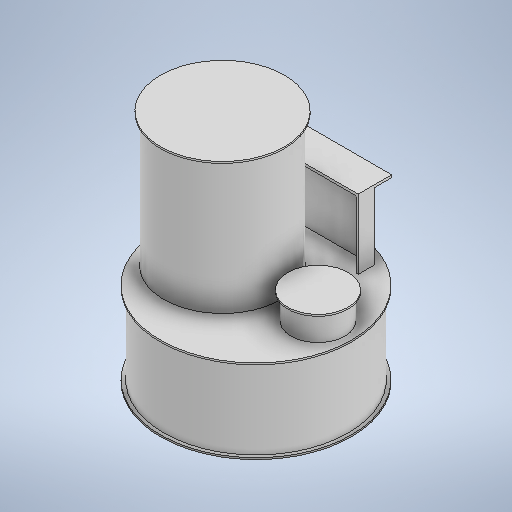
# Autodesk Inventor part: RDS-SPF-2-120-1000 Tank
Saved by Autodesk Inventor 2026 (Build 300175000, 175)
## iProperties
Created: 2026-10-27
Part Number: RDS-SPF-2-120-1000 Tank
Material: Типовые
Document SubType Name: Modeling
Designer: user
Density: 1 g/cm^3
Appearance: По умолчанию
Author: user
Autodesk Inventor part; units mm, degrees
ref_plane "YZ Plane" through (0, 0, 0) normal (1, 0, 0) x (0, 1, 0)
ref_plane "XZ Plane" through (0, 0, 0) normal (0, 1, 0) x (-1, 0, 0)
ref_plane "XY Plane" through (0, 0, 0) normal (0, 0, 1) x (1, 0, 0)
sketch "Эскиз1" plane through (0, 0, 0) normal (0, 1, 0) x (-1, 0, 0)
  circle A0 centre (0, 0) radius 550
  dimension "d0" = 1100
  constraints: 1 centre point, 1 coincident
  measures "d0" diameter of A0
extrude "Выдавливание1" add sketch "Эскиз1" along normal blind 500
sketch "Эскиз2" plane through (0, 500, 0) normal (0, 1, 0) x (1, 0, 0)
  circle A0 centre (-200, 0) radius 350
  point P0 (0, 0)
  dimension "d3" = 700
  dimension "d4" = 200
  dimension "d5" = 0
  constraints: 1 centre point
  measures "d3" diameter of A0
  measures "d4" distance of point (0, 0) A0.centre
  measures "d5" vertical distance of point (0, 0) A0.centre
extrude "Выдавливание2" add sketch "Эскиз2" along normal blind 800
shell "Оболочка1" thickness 10 removed faces 0
sketch "Эскиз3" plane through (0, 0, 0) normal (0, -1, 0) x (1, 0, 0)
  circle A0 centre (0, 0) radius 570
  dimension "d9" = 1140
  constraints: 1 centre point, 1 coincident
  measures "d9" diameter of A0
extrude "Выдавливание3" add sketch "Эскиз3" against normal blind 10
sketch "Эскиз4" plane through (0, 500, 0) normal (0, 1, 0) x (1, 0, 0)
  circle A0 centre (0, 0) radius 570
  dimension "d12" = 1140
  constraints: 1 centre point, 1 coincident
  measures "d12" diameter of A0
extrude "Выдавливание4" add sketch "Эскиз4" against normal blind 10
sketch "Эскиз5" plane through (-200, 1300, 0) normal (0, 1, 0) x (1, 0, 0)
  circle A0 centre (0, 0) radius 370
  point P0 (200, 0)
  dimension "d15" = 740
  dimension "d16" = 200
  dimension "d17" = 0
  constraints: 1 centre point
  measures "d15" diameter of A0
  measures "d16" distance of point (200, 0) A0.centre
  measures "d17" vertical distance of point (200, 0) A0.centre
extrude "Выдавливание5" add sketch "Эскиз5" against normal blind 10
sketch "Эскиз6" plane through (0, 500, 0) normal (0, 1, 0) x (1, 0, 0)
  circle A0 centre (370, 0) radius 160
  point P0 (0, 0)
  dimension "d20" = 320
  dimension "d21" = 0
  dimension "d22" = 370
  constraints: 1 centre point
  measures "d20" diameter of A0
  measures "d21" vertical distance of point (0, 0) A0.centre
  measures "d22" distance of point (0, 0) A0.centre
extrude "Выдавливание6" add sketch "Эскиз6" along normal blind 150
sketch "Эскиз7" plane through (370, 650, 0) normal (0, 1, 0) x (1, 0, 0)
  circle A0 centre (0, 0) radius 150
  point P0 (-370, 0)
  dimension "d25" = 300
  dimension "d26" = 370
  dimension "d27" = 0
  constraints: 1 centre point
  measures "d25" diameter of A0
  measures "d26" distance of A0.centre point (-370, 0)
  measures "d27" vertical distance of point (-370, 0) A0.centre
extrude "Выдавливание7" cut sketch "Эскиз7" against normal blind 160
sketch "Эскиз8" plane through (370, 650, 0) normal (0, 1, 0) x (1, 0, 0)
  circle A0 centre (0, 0) radius 180
  point P0 (-370, 0)
  dimension "d30" = 360
  dimension "d31" = 370
  dimension "d32" = 0
  constraints: 1 centre point
  measures "d30" diameter of A0
  measures "d31" distance of point (-370, 0) A0.centre
  measures "d32" vertical distance of point (-370, 0) A0.centre
extrude "Выдавливание8" add sketch "Эскиз8" along normal blind 10
sketch "Эскиз9" plane through (0, 500, 0) normal (0, 1, 0) x (1, 0, 0)
  line L0 (-250, 460) -> (250, 460)
  line L1 (250, 460) -> (250, 360)
  line L2 (250, 360) -> (240, 360)
  line L3 (240, 360) -> (240, 450)
  line L4 (240, 450) -> (-240, 450)
  line L5 (-240, 450) -> (-240, 360)
  line L6 (-240, 360) -> (-250, 360)
  line L7 (-250, 360) -> (-250, 460)
  point P0 (0, 0)
  dimension "d35" = 500
  dimension "d36" = 100
  dimension "d37" = 10
  dimension "d38" = 90
  dimension "d39" = 480
  dimension "d40" = 90
  dimension "d42" = 10
  dimension "d43" = 100
  dimension "d44" = 250
  dimension "d45" = 460
  constraints: 16 end point, 4 perpendicular, 2 horizontal, 1 point on line
  measures "d35" distance of L0.start L0.end
  measures "d36" distance of L0.end L1.end
  measures "d37" distance of L1.end L2.end
  measures "d38" distance of L2.end L3.end
  measures "d39" distance of L3.end L4.end
  measures "d40" distance of L4.end L5.end
  measures "d42" distance of L5.end L6.end
  measures "d43" distance of L6.end L0.start
  measures "d44" distance from line of L7 point (0, 0)
  measures "d45" distance from line of L0 point (0, 0)
extrude "Выдавливание9" add sketch "Эскиз9" along normal blind 400
sketch "Эскиз10" plane through (0, 900, 0) normal (0, 1, 0) x (1, 0, 0)
  line L0 (-250, 360) -> (250, 360)
  line L1 (250, 360) -> (250, 560)
  line L2 (250, 560) -> (-250, 560)
  line L3 (-250, 560) -> (-250, 360)
  line L4 (250, 460) -> (-250, 460) projected
  line L5 (-250, 360) -> (250, 560) construction
  line L6 (250, 360) -> (-250, 560) construction
  point P0 (0, 0)
  point P1 (0, 460)
  dimension "d48" = 500
  dimension "d49" = 200
  constraints: 12 end point, 3 midpoint, 2 parallel, 1 horizontal, 1 perpendicular
  measures "d48" distance of L2.end L1.end
  measures "d49" distance of L1.end L0.end
extrude "Выдавливание10" add sketch "Эскиз10" along normal blind 15
